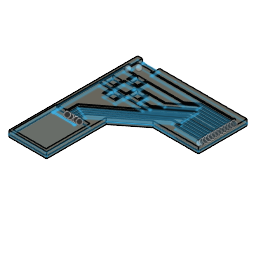
LeftController RedoV1 (Autodesk Fusion 360 design; units mm, degrees)
part number: 2026-09-02-15-08-17-802
Autodesk Fusion 360 part; units mm, degrees
sketch "Sketch1" plane through (0, 0, 0) normal (0, 0, 1) x (1, 0, 0)
  line L0 (-6, 5) -> (-2.9, 5)
  line L1 (-2.9, -5.6) -> (-6, -5.6)
  line L2 (-6, -5.6) -> (-6, 5)
  line L3 (-2.9, 5) -> (3, 5)
  line L4 (3, 5) -> (3, 1)
  line L5 (-0.7347, 1) -> (-2.9, -0.7)
  circle A0 centre (2.5, 1.6) radius 0.12
  circle A1 centre (2.5, 1.8545) radius 0.12
  circle A2 centre (2.5, 2.1091) radius 0.12
  circle A3 centre (2.5, 2.3636) radius 0.12
  circle A4 centre (2.5, 2.6182) radius 0.12
  circle A5 centre (2.5, 2.8727) radius 0.12
  circle A6 centre (2.5, 3.1273) radius 0.12
  circle A7 centre (2.5, 3.3818) radius 0.12
  circle A8 centre (2.5, 3.6364) radius 0.12
  circle A9 centre (2.5, 3.8909) radius 0.12
  circle A10 centre (2.5, 4.1455) radius 0.12
  circle A11 centre (2.5, 4.4) radius 0.12
  line L6 (-5.86, -5.4) -> (-3.14, -5.4)
  line L7 (-3.14, -5.4) -> (-3.14, -1.8)
  line L8 (-3.14, -1.8) -> (-5.86, -1.8)
  line L9 (-5.86, -1.8) -> (-5.86, -5.4)
  circle A12 centre (-4.5, -1.8) radius 0.125
  circle A13 centre (-4.25, -1.8) radius 0.125
  circle A14 centre (-4.75, -1.8) radius 0.125
  circle A15 centre (-4, -1.8) radius 0.125
  circle A16 centre (-5, -1.8) radius 0.125
  line L10 (-5.5, 5) -> (-4.3, 5)
  line L11 (-4.3, 5) -> (-4.3, 4.5)
  line L12 (-4.3, 4.5) -> (-5.5, 4.5)
  line L13 (-5.5, 4.5) -> (-5.5, 5)
  line L14 (-5.7, -1.8) -> (-5.8, -1.8)
  line L15 (-5.8, -1.8) -> (-5.8, 4.1)
  line L16 (-5.8, 4.1) -> (-5.7, 4.1)
  line L17 (-5.5, 4.5) -> (-5.4, 4.5)
  line L18 (-5.8, 4) -> (-5.8, 4.1)
  line L19 (-4.05, -1.8) -> (-3.95, -1.8)
  line L20 (-3.95, -1.8) -> (-3.95, -2.25)
  line L21 (-3.95, -2.25) -> (-4.05, -2.25)
  line L22 (-4.05, -2.25) -> (-4.05, -1.8)
  line L23 (-3.95, -2.25) -> (-5.7, -2.25)
  line L24 (-5.7, -2.25) -> (-5.7, -2.15)
  line L25 (-5.7, -2.15) -> (-3.95, -2.15)
  line L26 (-3.95, -2.15) -> (-3.95, -2.25)
  line L27 (-5.7, -2.25) -> (-5.8, -2.25)
  line L28 (-5.8, -2.25) -> (-5.8, -1.5)
  line L29 (-5.8, -1.5) -> (-5.7, -1.5)
  line L30 (-5.7, -1.5) -> (-5.7, -2.25)
  line L31 (-5.65, 2.6) -> (-4.9, 2.6)
  line L32 (-4.9, 2.6) -> (-4.9, 1.9)
  line L33 (-4.9, 1.9) -> (-5.65, 1.9)
  line L34 (-5.7, 1.9) -> (-5.7, 2.6)
  line L35 (-4.6, 1.6) -> (-3.9, 1.6)
  line L36 (-3.9, 1.6) -> (-3.9, 0.9)
  line L37 (-3.9, 0.9) -> (-4.6, 0.9)
  line L38 (-4.6, 0.9) -> (-4.6, 1.6)
  line L39 (-3.6, 2.6) -> (-2.9, 2.6)
  line L40 (-2.9, 2.6) -> (-2.9, 1.9)
  line L41 (-2.9, 1.9) -> (-3.6, 1.9)
  line L42 (-3.6, 1.9) -> (-3.6, 2.6)
  line L43 (-4.6, 3.6) -> (-3.9, 3.6)
  line L44 (-3.9, 3.6) -> (-3.9, 2.9)
  line L45 (-3.9, 2.9) -> (-4.6, 2.9)
  line L46 (-4.6, 2.9) -> (-4.6, 3.6)
  line L47 (2.5, 4.45) -> (-4.3, 4.45)
  line L48 (-4.3, 4.45) -> (-4.3, 4.35)
  line L49 (-4.3, 4.35) -> (2.5, 4.35)
  line L50 (2.5, 4.35) -> (2.5, 4.45)
  line L51 (-4.3, 5) -> (-4.2, 5)
  line L52 (-4.2, 5) -> (-4.2, 4.45)
  line L53 (-4.2, 4.45) -> (-4.3, 4.45)
  line L54 (-4.3, 4.45) -> (-4.3, 5)
  line L55 (-4.7, 2.9) -> (-4.8, 2.9)
  line L56 (-4.8, 2.9) -> (-4.8, 3.6)
  line L57 (-4.8, 3.6) -> (-4.7, 3.6)
  line L58 (-4.7, 3.6) -> (-4.7, 2.9)
  line L59 (-4.8, 3.5) -> (-5.7, 3.5)
  line L60 (-5.7, 3.5) -> (-5.7, 3.6)
  line L61 (-5.7, 3.6) -> (-4.8, 3.6)
  line L62 (-4.8, 3.6) -> (-4.8, 3.5)
  line L63 (-4.7, 0.9) -> (-4.8, 0.9)
  line L64 (-4.8, 0.9) -> (-4.8, 1.6)
  line L65 (-4.8, 1.6) -> (-4.7, 1.6)
  line L66 (-4.7, 1.6) -> (-4.7, 0.9)
  line L67 (-4.8, 1.5) -> (-5.7, 1.5)
  line L68 (-5.7, 1.5) -> (-5.7, 1.6)
  line L69 (-5.7, 1.6) -> (-4.8, 1.6)
  line L70 (-4.8, 1.6) -> (-4.8, 1.5)
  line L71 (-3.7, 1.9) -> (-3.8, 1.9)
  line L72 (-3.8, 1.9) -> (-3.8, 2.6)
  line L73 (-3.8, 2.6) -> (-3.7, 2.6)
  line L74 (-3.7, 2.6) -> (-3.7, 1.9)
  line L75 (-4.8, 1.6) -> (-4.7, 1.6)
  line L76 (-4.7, 1.6) -> (-4.7, 1.85)
  line L77 (-4.7, 1.85) -> (-4.8, 1.85)
  line L78 (-4.8, 1.85) -> (-4.8, 1.6)
  line L79 (-4.7, 1.85) -> (-3.7, 1.85)
  line L80 (-3.7, 1.85) -> (-3.7, 1.75)
  line L81 (-3.7, 1.75) -> (-4.7, 1.75)
  line L82 (-4.7, 1.75) -> (-4.7, 1.85)
  line L83 (-3.7, 1.85) -> (-3.8, 1.85)
  line L84 (-3.8, 1.85) -> (-3.8, 1.9)
  line L85 (-3.8, 1.9) -> (-3.7, 1.9)
  line L86 (-3.7, 1.9) -> (-3.7, 1.85)
  line L87 (2.5, 1.8) -> (0, 1.8)
  line L88 (0, 1.8) -> (0, 1.9)
  line L89 (0, 1.9) -> (2.5, 1.9)
  line L90 (2.5, 1.9) -> (2.5, 1.8)
  line L91 (-4.05, -1.8) -> (-3.95, -1.8)
  line L92 (-3.95, -1.8) -> (-3.95, -1.3)
  line L93 (-3.95, -1.3) -> (-4.05, -1.3)
  line L94 (-4.05, -1.3) -> (-4.05, -1.8)
  line L95 (-3.95, -1.3) -> (0, 1.8)
  line L96 (-4.05, -1.3) -> (0, 1.9)
  line L97 (-5.7, 4.1) -> (-5.7, 2.6)
  line L98 (-5.7, 1.9) -> (-5.7, -1.8)
  line L99 (-5.65, 2.6) -> (-5.65, 1.9)
  line L100 (2.5, 2.3) -> (0.3, 2.3)
  line L101 (0.3, 2.4) -> (2.5, 2.4)
  line L102 (2.5, 2.4) -> (2.5, 2.3)
  line L103 (2.5, 2.55) -> (0.3, 2.55)
  line L104 (0.3, 2.65) -> (2.5, 2.65)
  line L105 (2.5, 2.65) -> (2.5, 2.55)
  line L106 (2.5, 2.8) -> (0.3, 2.8)
  line L107 (2.5, 2.9) -> (2.5, 2.8)
  line L108 (2.5, 3.1) -> (0.3, 3.1)
  line L109 (0.3, 3.2) -> (2.5, 3.2)
  line L110 (2.5, 3.2) -> (2.5, 3.1)
  line L111 (0.3, 3.45) -> (2.5, 3.45)
  line L112 (2.5, 3.45) -> (2.5, 3.35)
  line L113 (0.3, 3.7) -> (2.5, 3.7)
  line L114 (2.5, 3.7) -> (2.5, 3.6)
  line L115 (2.5, 3.85) -> (0, 3.85)
  line L116 (0, 3.85) -> (0, 3.95)
  line L117 (0, 3.95) -> (2.5, 3.95)
  line L118 (2.5, 3.95) -> (2.5, 3.85)
  line L119 (2.5, 4.1) -> (0, 4.1)
  line L120 (0, 4.1) -> (0, 4.2)
  line L121 (0, 4.2) -> (2.5, 4.2)
  line L122 (2.5, 4.2) -> (2.5, 4.1)
  line L123 (-4.2, -1.8) -> (-4.3, -1.8)
  line L124 (-4.3, -1.8) -> (-4.3, -1.2)
  line L125 (-4.3, -1.2) -> (-4.2, -1.2)
  line L126 (-4.2, -1.2) -> (-4.2, -1.8)
  line L127 (-4.2, -1.2) -> (0.3, 2.3)
  line L128 (-4.3, -1.2) -> (0.3, 2.4)
  line L129 (0.3, 2.3) -> (0.3, 2.4)
  line L130 (-4.45, -1.8) -> (-4.55, -1.8)
  line L131 (-4.55, -1.8) -> (-4.55, -1.1)
  line L132 (-4.55, -1.1) -> (-4.45, -1.1)
  line L133 (-4.45, -1.1) -> (-4.45, -1.8)
  line L134 (-4.45, -1.1) -> (0.3, 2.55)
  line L135 (0.3, 2.65) -> (-4.55, -1.1)
  line L136 (0.3, 2.55) -> (0.3, 2.65)
  line L137 (-4.7, -1.8) -> (-4.8, -1.8)
  line L138 (-4.8, -1.8) -> (-4.8, -1)
  line L139 (-4.8, -1) -> (-4.7, -1)
  line L140 (-4.7, -1) -> (-4.7, -1.8)
  line L141 (-4.95, -1.8) -> (-5.05, -1.8)
  line L142 (-5.05, -1.8) -> (-5.05, -0.9)
  line L143 (-5.05, -0.9) -> (-4.95, -0.9)
  line L144 (-4.95, -0.9) -> (-4.95, -1.8)
  line L145 (-4.7, -1) -> (0.3, 2.8)
  line L146 (0.3, 2.9) -> (-4.8, -1)
  line L147 (0.3, 3.1) -> (0.3, 3.2)
  line L148 (0.3, 3.1) -> (-4.95, -0.9)
  line L149 (-5.05, -0.9) -> (0.3, 3.2)
  line L150 (0.3, 2.9) -> (0.3, 2.8)
  line L151 (0.3, 2.9) -> (2.5, 2.9)
  line L152 (-3.8, 1.6) -> (-3.7, 1.6)
  line L153 (-3.7, 1.6) -> (-3.7, 0.9)
  line L154 (-3.7, 0.9) -> (-3.8, 0.9)
  line L155 (-3.8, 0.9) -> (-3.8, 1.6)
  line L156 (-2.8, 2.6) -> (-2.7, 2.6)
  line L157 (-2.7, 2.6) -> (-2.7, 1.9)
  line L158 (-2.7, 1.9) -> (-2.8, 1.9)
  line L159 (-2.8, 1.9) -> (-2.8, 2.6)
  line L160 (-3.8, 3.6) -> (-3.7, 3.6)
  line L161 (-3.7, 3.6) -> (-3.7, 2.9)
  line L162 (-3.7, 2.9) -> (-3.8, 2.9)
  line L163 (-3.8, 2.9) -> (-3.8, 3.6)
  line L164 (-4.8, 2.6) -> (-4.7, 2.6)
  line L165 (-4.7, 2.6) -> (-4.7, 1.95)
  line L166 (-4.7, 1.95) -> (-4.8, 1.95)
  line L167 (-4.8, 1.95) -> (-4.8, 2.6)
  line L168 (-4.8, 2.7) -> (-4, 2.7)
  line L169 (-4, 2.7) -> (-4, 2.6)
  line L170 (-4, 2.6) -> (-4.8, 2.6)
  line L171 (-4.8, 2.6) -> (-4.8, 2.7)
  line L172 (-4.1, 2.8) -> (-4, 2.8)
  line L173 (-4, 2.8) -> (-4, 2.7)
  line L174 (-4, 2.7) -> (-4.1, 2.7)
  line L175 (-4.1, 2.7) -> (-4.1, 2.8)
  line L176 (-4, 2.8) -> (-2, 2.8)
  line L177 (-2, 2.7) -> (-4, 2.7)
  line L178 (-4, 2.7) -> (-4, 2.8)
  line L179 (-2.7, 2) -> (-2, 2)
  line L180 (-2, 1.9) -> (-2.7, 1.9)
  line L181 (-2.7, 1.9) -> (-2.7, 2)
  line L182 (-3.7, 1.6) -> (-2.2, 1.6)
  line L183 (-2.2, 1.5) -> (-3.7, 1.5)
  line L184 (-3.7, 1.5) -> (-3.7, 1.6)
  line L185 (0.3, 3.35) -> (-2.1, 1.5)
  line L186 (-2.1, 1.6) -> (0.3, 3.45)
  line L187 (-2.2, 1.5) -> (-2.1, 1.5)
  line L188 (-2.1, 1.6) -> (-2.2, 1.6)
  line L189 (2.5, 3.35) -> (0.3, 3.35)
  line L190 (0.3, 3.45) -> (0.3, 3.35)
  line L191 (0.3, 3.6) -> (-1.9, 1.9)
  line L192 (-1.9, 1.9) -> (-1.9, 2)
  line L193 (-1.9, 2) -> (0.3, 3.7)
  line L194 (0.3, 3.6) -> (0.3, 3.7)
  line L195 (-1.9, 2) -> (-2, 2)
  line L196 (-2, 1.9) -> (-1.9, 1.9)
  line L197 (2.5, 3.6) -> (0.3, 3.6)
  line L198 (0, 3.85) -> (-1.5, 2.7)
  line L199 (-1.5, 2.7) -> (-1.5, 2.8)
  line L200 (-1.5, 2.8) -> (0, 3.95)
  line L201 (-1.5, 2.7) -> (-2, 2.7)
  line L202 (-2, 2.8) -> (-1.5, 2.8)
  line L203 (0, 4.1) -> (-0.8, 3.5)
  line L204 (-0.8, 3.5) -> (-3.7, 3.5)
  line L205 (-3.7, 3.6) -> (-0.8, 3.6)
  line L206 (-0.8, 3.6) -> (0, 4.2)
  line L207 (-0.7347, 1) -> (1, 1)
  line L208 (3, 1) -> (-0.7347, 1)
  line L209 (-2.9, -0.7) -> (-2.9, -5.6)
  line L210 (-2.9, 1.5) -> (-2.9, 1.6)
  line L211 (-2.9, 1.9) -> (-2.9, 2.6)
  line L212 (-2.9, 2.6) -> (-2.9, 1.9)
  line L213 (-5.6, 5) -> (-5.5, 5)
  line L214 (-5.5, 5) -> (-5.5, 4)
  line L215 (-5.5, 4) -> (-5.6, 4)
  line L216 (-5.6, 4) -> (-5.6, 5)
  line L217 (-5.8, 4.1) -> (-5.5, 4.1)
  line L218 (-5.5, 4.1) -> (-5.5, 4)
  line L219 (-5.5, 4) -> (-5.8, 4)
  line L220 (-5.8, 4) -> (-5.8, 4.1)
  line L221 (2.5, 1.55) -> (0.5, 1.55)
  line L222 (0.5, 1.55) -> (0.5, 1.65)
  line L223 (0.5, 1.65) -> (2.5, 1.65)
  line L224 (2.5, 1.65) -> (2.5, 1.55)
  line L225 (2.5, 2.05) -> (0.5, 2.05)
  line L226 (0.5, 2.05) -> (0.5, 2.15)
  line L227 (0.5, 2.15) -> (2.5, 2.15)
  line L228 (2.5, 2.15) -> (2.5, 2.05)
  point P0 (2.5, 1.8545)
  point P1 (2.5, 2.1091)
  point P2 (2.5, 2.3636)
  point P3 (2.5, 2.6182)
  point P4 (2.5, 2.8727)
  point P5 (2.5, 3.1273)
  point P6 (2.5, 3.3818)
  point P7 (2.5, 3.6364)
  point P8 (2.5, 3.8909)
  point P9 (2.5, 4.1455)
  point P10 (2.5, 4.4)
  dimension "d1" = 0.24
  dimension "d4" = 0
  dimension "d5" = 2.8
  dimension "d6" = 0.24
  dimension "d7" = 0.24
  dimension "d8" = 0.24
  dimension "d9" = 0.24
  dimension "d10" = 0.24
  dimension "d11" = 0.24
  dimension "d12" = 0.24
  dimension "d13" = 0.24
  dimension "d14" = 0.24
  dimension "d15" = 0.24
  dimension "d16" = 0.24
  dimension "d17" = 0.25
  dimension "d18" = 0.25
  dimension "d19" = 0.25
  dimension "d20" = 0.25
  dimension "d21" = 0.25
  constraint horizontal L0
  constraint horizontal L1
  constraint vertical L2
  constraint horizontal L3
  constraint vertical L4
  constraint horizontal L208
  constraint vertical L210
  constraint coincident L207.end L208
  constraint coincident P0 A1.centre
  constraint coincident P1 A2.centre
  constraint coincident P2 A3.centre
  constraint coincident P3 A4.centre
  constraint coincident P4 A5.centre
  constraint coincident P5 A6.centre
  constraint coincident P6 A7.centre
  constraint coincident P7 A8.centre
  constraint coincident P8 A9.centre
  constraint coincident P9 A10.centre
  constraint coincident P10 A11.centre
  constraint horizontal L6
  constraint vertical L7
  constraint horizontal L8
  constraint vertical L9
  constraint midpoint L8 A12.centre
  constraint coincident L8 A13.centre
  constraint coincident L8 A14.centre
  constraint coincident L8 A15.centre
  constraint coincident L8 A16.centre
  constraint horizontal L10
  constraint vertical L11
  constraint horizontal L12
  constraint vertical L13
  constraint coincident L0 L10.start
  constraint horizontal L14
  constraint vertical L15
  constraint horizontal L16
  constraint vertical L97
  constraint coincident L8 L14.start
  constraint horizontal L17
  constraint vertical L18
  constraint horizontal L19
  constraint vertical L20
  constraint horizontal L21
  constraint vertical L22
  constraint coincident L8 L19.start
  constraint horizontal L23
  constraint vertical L24
  constraint horizontal L25
  constraint vertical L26
  constraint horizontal L27
  constraint vertical L28
  constraint horizontal L29
  constraint vertical L30
  constraint coincident L23 L24.start
  constraint horizontal L31
  constraint vertical L32
  constraint horizontal L33
  constraint vertical L34
  constraint horizontal L35
  constraint vertical L36
  constraint horizontal L37
  constraint vertical L38
  constraint horizontal L39
  constraint vertical L40
  constraint horizontal L41
  constraint vertical L42
  constraint horizontal L43
  constraint vertical L44
  constraint horizontal L45
  constraint vertical L46
  constraint horizontal L47
  constraint vertical L48
  constraint horizontal L49
  constraint vertical L50
  constraint horizontal L51
  constraint vertical L52
  constraint horizontal L53
  constraint vertical L54
  constraint coincident L47 L52.end
  constraint horizontal L55
  constraint vertical L56
  constraint horizontal L57
  constraint vertical L58
  constraint horizontal L59
  constraint vertical L60
  constraint horizontal L61
  constraint vertical L62
  constraint coincident L60.end L97
  constraint coincident L56 L59.start
  constraint horizontal L63
  constraint vertical L64
  constraint horizontal L65
  constraint vertical L66
  constraint horizontal L67
  constraint vertical L68
  constraint horizontal L69
  constraint vertical L70
  constraint coincident L64 L67.start
  constraint horizontal L71
  constraint vertical L72
  constraint horizontal L73
  constraint vertical L74
  constraint horizontal L75
  constraint vertical L76
  constraint horizontal L77
  constraint vertical L78
  constraint horizontal L79
  constraint vertical L80
  constraint horizontal L81
  constraint vertical L82
  constraint horizontal L83
  constraint vertical L84
  constraint horizontal L85
  constraint vertical L86
  constraint horizontal L87
  constraint vertical L88
  constraint horizontal L89
  constraint vertical L90
  constraint horizontal L91
  constraint vertical L92
  constraint horizontal L93
  constraint vertical L94
  constraint collinear L97 L98
  constraint perpendicular L33 L99
  constraint horizontal L100
  constraint horizontal L101
  constraint vertical L102
  constraint horizontal L103
  constraint horizontal L104
  constraint vertical L105
  constraint horizontal L106
  constraint vertical L107
  constraint horizontal L108
  constraint horizontal L109
  constraint vertical L110
  constraint horizontal L189
  constraint horizontal L111
  constraint vertical L112
  constraint horizontal L197
  constraint horizontal L113
  constraint vertical L114
  constraint horizontal L115
  constraint vertical L116
  constraint horizontal L117
  constraint vertical L118
  constraint horizontal L119
  constraint vertical L120
  constraint horizontal L121
  constraint vertical L122
  constraint horizontal L123
  constraint vertical L124
  constraint horizontal L125
  constraint vertical L126
  constraint coincident L8 L123.start
  constraint perpendicular L101 L129
  constraint horizontal L130
  constraint vertical L131
  constraint horizontal L132
  constraint vertical L133
  constraint coincident L8 L130.start
  constraint perpendicular L104 L136
  constraint horizontal L137
  constraint vertical L138
  constraint horizontal L139
  constraint vertical L140
  constraint coincident L8 L137.start
  constraint horizontal L141
  constraint vertical L142
  constraint horizontal L143
  constraint vertical L144
  constraint coincident L8 L141.start
  constraint perpendicular L109 L147
  constraint perpendicular L106 L150
  constraint horizontal L152
  constraint vertical L153
  constraint horizontal L154
  constraint vertical L155
  constraint horizontal L156
  constraint vertical L157
  constraint horizontal L158
  constraint vertical L159
  constraint horizontal L160
  constraint vertical L161
  constraint horizontal L162
  constraint vertical L163
  constraint horizontal L164
  constraint vertical L165
  constraint horizontal L166
  constraint vertical L167
  constraint horizontal L168
  constraint vertical L169
  constraint horizontal L170
  constraint vertical L171
  constraint horizontal L172
  constraint vertical L173
  constraint horizontal L174
  constraint vertical L175
  constraint horizontal L176
  constraint horizontal L177
  constraint vertical L178
  constraint horizontal L179
  constraint horizontal L180
  constraint vertical L181
  constraint coincident L157 L179.start
  constraint horizontal L182
  constraint horizontal L183
  constraint vertical L184
  constraint parallel L185 L186
  constraint coincident L186 L111.start
  constraint perpendicular L180 L192
  constraint parallel L191 L193
  constraint perpendicular L113 L194
  constraint perpendicular L192 L196
  constraint perpendicular L115 L199
  constraint parallel L198 L200
  constraint perpendicular L199 L202
  constraint coincident L161 L204.end
  constraint perpendicular L161 L204
  constraint perpendicular L161 L205
  constraint parallel L203 L206
  constraint coincident L183 L210.start
  constraint coincident L182 L210.end
  constraint collinear L210 L211
  constraint horizontal L213
  constraint vertical L214
  constraint horizontal L215
  constraint vertical L216
  constraint coincident L0 L213.start
  constraint horizontal L217
  constraint vertical L218
  constraint horizontal L219
  constraint vertical L220
  constraint horizontal L221
  constraint vertical L222
  constraint horizontal L223
  constraint vertical L224
  constraint horizontal L225
  constraint vertical L226
  constraint horizontal L227
  constraint vertical L228
  measures "d1" diameter of A0
  measures "d6" diameter of A1
  measures "d7" diameter of A2
  measures "d8" diameter of A3
  measures "d9" diameter of A4
  measures "d10" diameter of A5
  measures "d11" diameter of A6
  measures "d12" diameter of A7
  measures "d13" diameter of A8
  measures "d14" diameter of A9
  measures "d15" diameter of A10
  measures "d16" diameter of A11
  measures "d17" diameter of A12
  measures "d18" diameter of A13
  measures "d19" diameter of A14
  measures "d20" diameter of A15
  measures "d21" diameter of A16
extrude "Extrude1" add sketch "Sketch1" along normal blind 0.3 contours L0 L1 L2 L3 L4 L5 A1 A3 A4 A5 A6 A11 L6 L7 L8 L9 A12 A13 A14 A15 A16 L12 L15 L16 L17 L18 L28 L30 L34 L47 L48 L49 L52 L54 L55 L56 L57 L58 L59 L61 L63 L64 L66 L67 L69 L72 L73 L74 L76 L77 L78 L79 L80 L81 L84 L86 L87 L89 L92 L94 L95 L96 L97 L98 L100 L101 L103 L104 L106 L108 L109 L124 L126 L127 L128 L131 L133 L134 L135 L138 L140 L142 L144 L145 L146 L148 L149 L151 L207 L208 L209 L214 L215 L216 L217 L218 L219 L220 makes body 1
extrude "Extrude2" add sketch "Sketch1" against normal blind 0.2 separate body contours L0 L1 L2 L3 L4 L5 A1 A3 A4 A5 A6 A11 L6 L7 L8 L9 A12 A13 A14 A15 A16 L12 L15 L16 L17 L18 L28 L30 L34 L47 L48 L49 L52 L54 L55 L56 L57 L58 L59 L61 L63 L64 L66 L67 L69 L72 L73 L74 L76 L77 L78 L79 L80 L81 L84 L86 L87 L89 L92 L94 L95 L96 L97 L98 L100 L101 L103 L104 L106 L108 L109 L124 L126 L127 L128 L131 L133 L134 L135 L138 L140 L142 L144 L145 L146 L148 L149 L151 L207 L208 L209 L214 L215 L216 L217 L218 L219 L220 | L0 L13 L213 L214 L216 L217 | L0 L10 L11 L12 L13 L17 L54 L214 | L214 L215 L216 L217 L218 L219 | L97 L216 L217 L219 | L0 L11 L47 L51 L52 L53 L54 | L15 L16 L18 L97 L217 L219 L220 | L15 L29 L34 L60 L68 L97 L98 L219 | A11 L47 L48 L49 L53 | L56 L59 L60 L61 L62 L97 | A11 L47 L49 L50 | A11 L47 L49 L50 | L55 L56 L57 L58 L62 | L8 L14 L15 L28 L29 L30 L98 | L6 L7 L8 L9 A15 L20 L21 L23 L26 L27 L28 | L8 L14 L24 L27 L28 L30 | L8 A12 A13 A14 A15 A16 L22 L25 L30 | L64 L67 L68 L69 L70 L98 | L8 A16 L142 | L8 A16 L141 | L22 L23 L24 L25 L30 | L63 L64 L65 L66 L70 L75 | L65 L75 L76 L77 L78 L82 | L8 A16 L141 L142 L144 | A16 L142 L143 L144 | L8 A14 L138 | L8 A14 L137 | L8 A16 L144 | L20 L21 L22 L23 L25 L26 | A15 L20 L22 L25 | L143 L147 L148 L149 | L8 A14 L137 L138 L140 | L8 A12 L131 | L8 A12 L130 | L8 A14 L140 | A14 L138 L139 L140 | L8 A15 L19 L20 L22 L91 | L8 A15 L22 | L76 L79 L80 L81 L82 L83 | A6 L108 L109 L147 | L8 A12 L130 L131 L133 | L8 A13 L124 | L8 A12 L133 | L8 A13 L123 | A12 L131 L132 L133 | L139 L145 L146 L150 | L8 A15 L94 | L8 A13 L126 | L8 A15 L20 | L8 A15 L19 L91 L92 L94 | L8 A15 L92 | L71 L79 L83 L84 L85 L86 | A6 L108 L109 L110 | A6 L108 L109 L110 | L8 A13 L123 L124 L126 | A13 L124 L125 L126 | L132 L134 L135 L136 | A5 L106 L150 L151 | A15 L92 L93 L94 | L71 L72 L73 L74 L85 | L125 L127 L128 L129 | A4 L103 L104 L136 | A5 L106 L107 L151 | A5 L106 L107 L151 | L88 L93 L95 L96 | A3 L100 L101 L129 | A4 L103 L104 L105 | A4 L103 L104 L105 | A1 L87 L88 L89 | A3 L100 L101 L102 | A3 L100 L101 L102 | A1 L87 L89 L90 | A1 L87 L89 L90 | A0 L221 L223 L224 | A0 L221 L223 L224 | A0 L221 L222 L223 | A2 L225 L227 L228 | A2 L225 L227 L228 | A2 L225 L226 L227 | A7 L111 L112 L189 | A7 L111 L112 L189 | A7 L111 L189 L190 | L182 L183 L185 L186 L187 L188 L190 L210 | L153 L182 L183 L184 L210 | L152 L153 L154 L155 L184 | A8 L113 L114 L197 | A8 L113 L114 L197 | A8 L113 L194 L197 | L191 L192 L193 L194 | L157 L179 L180 L181 L192 L195 L196 | L156 L157 L158 L159 L181 | A9 L115 L117 L118 | A9 L115 L117 L118 | A9 L115 L116 L117 | L116 L198 L199 L200 | L173 L176 L177 L178 L199 L201 L202 | L168 L172 L173 L174 L175 L178 | L164 L168 L169 L170 L171 L174 | L164 L165 L166 L167 L170 | A10 L119 L121 L122 | A10 L119 L121 L122 | A10 L119 L120 L121 | L120 L161 L203 L204 L205 L206 | L160 L161 L162 L163 | L31 L32 L33 L99 | L35 L36 L37 L38 | L39 L40 L41 L42 L211 L212 | L43 L44 L45 L46 makes body 2
